Autodesk Fusion 360 part; units mm, degrees
(part 2 of 2)
component "vacuum cup" placed x (1, 0, 0) y (0, 1, 0) z (0, 0, 1) at (-180, 120, 127)
component "vacuum cup stem" placed x (1, 0, 0) y (0, 1, 0) z (0, 0, 1) at (-180, 120, 151)
component "S3 A2 upper proximity switch (code pending)" placed x (1, 0, 0) y (0, 1, 0) z (0, 0, 1) at (-207, 120, 255)
component "S4 A2 lower proximity switch (code pending)" placed x (1, 0, 0) y (0, 1, 0) z (0, 0, 1) at (-207, 120, 185)
component "motor Y carriage" placed x (1, 0, 0) y (0, 1, 0) z (0, 0, 1) at (-180, 435, 320)
component "motor X rear" placed x (1, 0, 0) y (0, 1, 0) z (0, 0, 1) at (330, 425, 320)
component "motor X front" placed x (1, 0, 0) y (0, 1, 0) z (0, 0, 1) at (330, 10, 320)
component "bin R1C1" placed x (1, 0, 0) y (0, 1, 0) z (0, 0, 1) at (80, 75, 12)
component "bin R1C2" placed x (1, 0, 0) y (0, 1, 0) z (0, 0, 1) at (195, 75, 12)
component "bin R2C1" placed x (1, 0, 0) y (0, 1, 0) z (0, 0, 1) at (80, 190, 12)
component "bin R2C2" placed x (1, 0, 0) y (0, 1, 0) z (0, 0, 1) at (195, 190, 12)
component "bin R3C1" placed x (1, 0, 0) y (0, 1, 0) z (0, 0, 1) at (80, 305, 12)
component "bin R3C2" placed x (1, 0, 0) y (0, 1, 0) z (0, 0, 1) at (195, 305, 12)
component "PS1 bracket foot" placed x (1, 0, 0) y (0, 1, 0) z (0, 0, 1) at (-246, -65, 22)
component "PS1 bracket upright" placed x (1, 0, 0) y (0, 1, 0) z (0, 0, 1) at (-242, -65, 26)
component "PS1 YF-KJ E3F-DS30C4 M18 body" placed x (0, 0, -1) y (0, 1, 0) z (1, 0, 0) at (-302, -65, 65)
component "PS1 locking ring" placed x (0, 0, -1) y (0, 1, 0) z (1, 0, 0) at (-244, -65, 65)
component "PS1 optical face" placed x (0, 0, -1) y (0, 1, 0) z (1, 0, 0) at (-236, -65, 65)
component "PS2 bracket foot" placed x (1, 0, 0) y (0, 1, 0) z (0, 0, 1) at (-246, 170, 22)
component "PS2 bracket upright" placed x (1, 0, 0) y (0, 1, 0) z (0, 0, 1) at (-242, 170, 26)
component "PS2 YF-KJ E3F-DS30C4 M18 body" placed x (0, 0, -1) y (0, 1, 0) z (1, 0, 0) at (-302, 170, 65)
component "PS2 locking ring" placed x (0, 0, -1) y (0, 1, 0) z (1, 0, 0) at (-244, 170, 65)
component "PS2 optical face" placed x (0, 0, -1) y (0, 1, 0) z (1, 0, 0) at (-236, 170, 65)
component "A1 front pusher cylinder" placed x (1, 0, 0) y (0, 1, 0) z (0, 0, 1) at (-180, -435, 20)
component "A1 pusher rod" placed x (1, 0, 0) y (0, 1, 0) z (0, 0, 1) at (-180, -431, 55)
component "A1 pusher plate" placed x (1, 0, 0) y (0, 1, 0) z (0, 0, 1) at (-180, -377, 49)
component "S1 A1 retracted switch (code pending)" placed x (1, 0, 0) y (0, 1, 0) z (0, 0, 1) at (-206, -480, 37)
component "S2 A1 extended switch (code pending)" placed x (1, 0, 0) y (0, 1, 0) z (0, 0, 1) at (-206, -390, 37)
component "Y1 4V210-08 manifold" placed x (1, 0, 0) y (0, 1, 0) z (0, 0, 1) at (0, -455, 12)
component "Y1 4V210-08 aluminum body" placed x (1, 0, 0) y (0, 1, 0) z (0, 0, 1) at (-22, -455, 28)
component "Y1 spring cap" placed x (1, 0, 0) y (0, 1, 0) z (0, 0, 1) at (-64, -455, 28)
component "Y1 pilot and manual override" placed x (1, 0, 0) y (0, 1, 0) z (0, 0, 1) at (23, -455, 28)
component "Y1 DC24V 4.8W 200mA coil" placed x (1, 0, 0) y (0, 1, 0) z (0, 0, 1) at (55, -455, 28)
component "Y1 DIN plug" placed x (1, 0, 0) y (0, 1, 0) z (0, 0, 1) at (55, -455, 56)
component "Y1 manual button" placed x (1, 0, 0) y (0, 1, 0) z (0, 0, 1) at (23, -455, 52)
component "Y1 port A fitting" placed x (1, 0, 0) y (0, 1, 0) z (0, 0, 1) at (-43, -455, 52)
component "Y1 port A collet" placed x (1, 0, 0) y (0, 1, 0) z (0, 0, 1) at (-43, -455, 63)
component "Y1 port B fitting" placed x (1, 0, 0) y (0, 1, 0) z (0, 0, 1) at (-4, -455, 52)
component "Y1 port B collet" placed x (1, 0, 0) y (0, 1, 0) z (0, 0, 1) at (-4, -455, 63)
component "Y2 4V210-08 manifold" placed x (1, 0, 0) y (0, 1, 0) z (0, 0, 1) at (0, -415, 12)
component "Y2 4V210-08 aluminum body" placed x (1, 0, 0) y (0, 1, 0) z (0, 0, 1) at (-22, -415, 28)
component "Y2 spring cap" placed x (1, 0, 0) y (0, 1, 0) z (0, 0, 1) at (-64, -415, 28)
component "Y2 pilot and manual override" placed x (1, 0, 0) y (0, 1, 0) z (0, 0, 1) at (23, -415, 28)
component "Y2 DC24V 4.8W 200mA coil" placed x (1, 0, 0) y (0, 1, 0) z (0, 0, 1) at (55, -415, 28)
component "Y2 DIN plug" placed x (1, 0, 0) y (0, 1, 0) z (0, 0, 1) at (55, -415, 56)
component "Y2 manual button" placed x (1, 0, 0) y (0, 1, 0) z (0, 0, 1) at (23, -415, 52)
component "Y2 port A fitting" placed x (1, 0, 0) y (0, 1, 0) z (0, 0, 1) at (-43, -415, 52)
component "Y2 port A collet" placed x (1, 0, 0) y (0, 1, 0) z (0, 0, 1) at (-43, -415, 63)
component "Y2 port B fitting" placed x (1, 0, 0) y (0, 1, 0) z (0, 0, 1) at (-4, -415, 52)
component "Y2 port B collet" placed x (1, 0, 0) y (0, 1, 0) z (0, 0, 1) at (-4, -415, 63)
component "PLC 1214C envelope" placed x (1, 0, 0) y (0, 1, 0) z (0, 0, 1) at (320, 190, 12)
component "button station envelope" placed x (1, 0, 0) y (0, 1, 0) z (0, 0, 1) at (320, -200, 12)
component "button EStop" placed x (1, 0, 0) y (0, 1, 0) z (0, 0, 1) at (320, -135, 48)
component "button Reset" placed x (1, 0, 0) y (0, 1, 0) z (0, 0, 1) at (320, -178, 48)
component "button Stop" placed x (1, 0, 0) y (0, 1, 0) z (0, 0, 1) at (320, -221, 48)
component "button Start" placed x (1, 0, 0) y (0, 1, 0) z (0, 0, 1) at (320, -264, 48)
named bodies: "base board", "long conveyor chassis", "long green belt", "front conveyor chassis", "front green belt", "long conveyor side rail -1", "front conveyor side rail -1 left", "front conveyor side rail -1 right", "long conveyor side rail 1", "front conveyor side rail 1 left", "front conveyor side rail 1 right", "front conveyor roller -330", "front conveyor roller 250", "long conveyor roller -265", "long conveyor roller 225", "front conveyor DC motor", "long conveyor DC motor", "L transfer guide", "gantry post left front", "gantry post left rear", "gantry post right front", "gantry post right rear", "gantry X rail front", "gantry X rail rear", "right Y guide", "moving Y rail", "pick carriage", "moving Y rail lower guide", "A2 carriage mount", "A2 TN10X75-S twin rod body", "A2 rod at x -191", "A2 rod at x -169", "A2 rod end plate", "vacuum cup", "vacuum cup stem", "S3 A2 upper proximity switch (code pending)", "S4 A2 lower proximity switch (code pending)", "motor Y carriage", "motor X rear", "motor X front", "bin R1C1 floor", "bin R1C1 side wall -1", "bin R1C1 end wall -1", "bin R1C1 side wall 1", "bin R1C1 end wall 1", "bin R1C2 floor", "bin R1C2 side wall -1", "bin R1C2 end wall -1", "bin R1C2 side wall 1", "bin R1C2 end wall 1", "bin R2C1 floor", "bin R2C1 side wall -1", "bin R2C1 end wall -1", "bin R2C1 side wall 1", "bin R2C1 end wall 1", "bin R2C2 floor", "bin R2C2 side wall -1", "bin R2C2 end wall -1", "bin R2C2 side wall 1", "bin R2C2 end wall 1", "bin R3C1 floor", "bin R3C1 side wall -1", "bin R3C1 end wall -1", "bin R3C1 side wall 1", "bin R3C1 end wall 1", "bin R3C2 floor", "bin R3C2 side wall -1", "bin R3C2 end wall -1", "bin R3C2 side wall 1", "bin R3C2 end wall 1", "PS1 bracket foot", "PS1 bracket upright", "PS1 YF-KJ E3F-DS30C4 M18 body", "PS1 locking ring", "PS1 optical face", "PS2 bracket foot", "PS2 bracket upright", "PS2 YF-KJ E3F-DS30C4 M18 body", "PS2 locking ring", "PS2 optical face", "A1 front pusher cylinder", "A1 pusher rod", "A1 pusher plate", "S1 A1 retracted switch (code pending)", "S2 A1 extended switch (code pending)", "Y1 4V210-08 manifold", "Y1 4V210-08 aluminum body", "Y1 spring cap", "Y1 pilot and manual override", "Y1 DC24V 4.8W 200mA coil", "Y1 DIN plug", "Y1 manual button", "Y1 port A fitting", "Y1 port A collet", "Y1 port B fitting", "Y1 port B collet", "Y2 4V210-08 manifold", "Y2 4V210-08 aluminum body", "Y2 spring cap", "Y2 pilot and manual override", "Y2 DC24V 4.8W 200mA coil", "Y2 DIN plug", "Y2 manual button", "Y2 port A fitting", "Y2 port A collet", "Y2 port B fitting", "Y2 port B collet", "PLC 1214C envelope", "button station envelope", "button EStop", "button Reset", "button Stop", "button Start"
